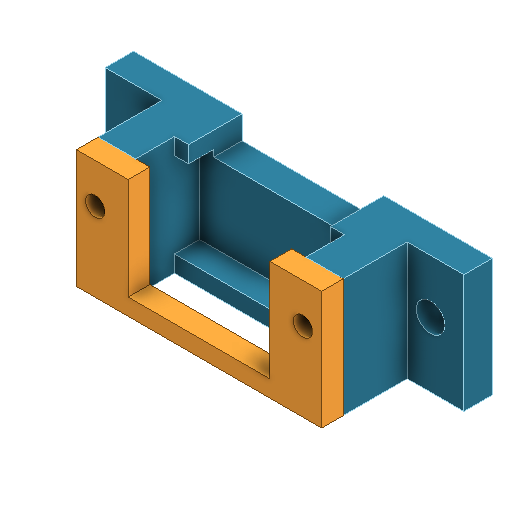
# Autodesk Inventor part: MI-305_Mount_A_Flat_Screw
Saved by Autodesk Inventor 2027 (Build 310192060, 192F)
## iProperties
Created: 2026-11-23
Part Number: MI-305_Mount_A_Flat_Screw
Material: 一般
Document SubType Name: Modeling
Designer: 王翊丞
Density: 1 g/cm^3
Appearance: 預設
Title: MI-305 A 平放螺絲款
Author: 王翊丞
Comments: MI-305 專用。以兩顆 M2 螺絲固定壓片。模型內的底座與壓片是獨立實體。
Autodesk Inventor part; units mm, degrees
sketch "平放承板草圖" plane through (0, 0, 0) normal (0, 0, 1) x (1, 0, 0)
  line L0 (-21.5, -11.95) -> (21.5, -11.95)
  line L1 (21.5, -11.95) -> (21.5, 2.25)
  line L2 (21.5, 2.25) -> (-21.5, 2.25)
  line L3 (-21.5, 2.25) -> (-21.5, -11.95)
  point P0 (0, 0)
  dimension "d0" = 21.5
  dimension "d1" = 11.95
  dimension "d2" = 43
  dimension "d3" = 14.2
  constraints: 8 end point, 2 parallel, 1 horizontal, 1 perpendicular, 1 other
  measures "d0" horizontal distance of point (0, 0) L0.start
  measures "d1" vertical distance of point (0, 0) L0.start
  measures "d2" distance of L0.start L0.end
  measures "d3" distance of L0.end L1.end
extrude "平放承板" add sketch "平放承板草圖" along normal blind 3.4
ref_plane "承托面" through (0, 0, 3.4) normal (0, 0, 1) x (1, 0, 0)
sketch "USB 插拔避空草圖" plane through (0, 0, 3.4) normal (0, 0, 1) x (1, 0, 0)
  line L0 (-8.5, -0.55) -> (8.5, -0.55)
  line L1 (8.5, -0.55) -> (8.5, 3.25)
  line L2 (8.5, 3.25) -> (-8.5, 3.25)
  line L3 (-8.5, 3.25) -> (-8.5, -0.55)
  point P0 (0, 0)
  dimension "d7" = 8.5
  dimension "d8" = 0.55
  dimension "d9" = 17
  dimension "d10" = 3.8
  constraints: 8 end point, 2 parallel, 1 horizontal, 1 perpendicular, 1 other
  measures "d7" horizontal distance of point (0, 0) L0.start
  measures "d8" vertical distance of point (0, 0) L0.start
  measures "d9" distance of L0.start L0.end
  measures "d10" distance of L0.end L1.end
extrude "USB 插拔避空" cut sketch "USB 插拔避空草圖" against normal blind 3.4
sketch "左側定位壁草圖" plane through (0, 0, 3.4) normal (0, 0, 1) x (1, 0, 0)
  line L0 (-14.7, -11.95) -> (-10.2, -11.95)
  line L1 (-10.2, -11.95) -> (-10.2, 2.25)
  line L2 (-10.2, 2.25) -> (-14.7, 2.25)
  line L3 (-14.7, 2.25) -> (-14.7, -11.95)
  point P0 (0, 0)
  dimension "d13" = 14.7
  dimension "d14" = 11.95
  dimension "d15" = 4.5
  dimension "d16" = 14.2
  constraints: 8 end point, 2 parallel, 1 horizontal, 1 perpendicular, 1 other
  measures "d13" horizontal distance of point (0, 0) L0.start
  measures "d14" vertical distance of point (0, 0) L0.start
  measures "d15" distance of L0.start L0.end
  measures "d16" distance of L0.end L1.end
extrude "左側定位壁" add sketch "左側定位壁草圖" along normal blind 7.65
sketch "右側定位壁草圖" plane through (0, 0, 3.4) normal (0, 0, 1) x (1, 0, 0)
  line L0 (10.2, -11.95) -> (14.7, -11.95)
  line L1 (14.7, -11.95) -> (14.7, 2.25)
  line L2 (14.7, 2.25) -> (10.2, 2.25)
  line L3 (10.2, 2.25) -> (10.2, -11.95)
  point P0 (0, 0)
  dimension "d19" = 10.2
  dimension "d20" = 11.95
  dimension "d21" = 4.5
  dimension "d22" = 14.2
  constraints: 8 end point, 2 parallel, 1 horizontal, 1 perpendicular, 1 other
  measures "d19" horizontal distance of point (0, 0) L0.start
  measures "d20" vertical distance of point (0, 0) L0.start
  measures "d21" distance of L0.start L0.end
  measures "d22" distance of L0.end L1.end
extrude "右側定位壁" add sketch "右側定位壁草圖" along normal blind 7.65
sketch "弧端定位擋塊草圖" plane through (0, 0, 3.4) normal (0, 0, 1) x (1, 0, 0)
  line L0 (-10.2, -11.95) -> (10.2, -11.95)
  line L1 (10.2, -11.95) -> (10.2, -9.95)
  line L2 (10.2, -9.95) -> (-10.2, -9.95)
  line L3 (-10.2, -9.95) -> (-10.2, -11.95)
  point P0 (0, 0)
  dimension "d25" = 10.2
  dimension "d26" = 11.95
  dimension "d27" = 20.4
  dimension "d28" = 2
  constraints: 8 end point, 2 parallel, 1 horizontal, 1 perpendicular, 1 other
  measures "d25" horizontal distance of point (0, 0) L0.start
  measures "d26" vertical distance of point (0, 0) L0.start
  measures "d27" distance of L0.start L0.end
  measures "d28" distance of L0.end L1.end
extrude "弧端定位擋塊" add sketch "弧端定位擋塊草圖" along normal blind 3
sketch "左肩面擋塊草圖" plane through (0, 0, 3.4) normal (0, 0, 1) x (1, 0, 0)
  line L0 (-10.2, 0.25) -> (-8.5, 0.25)
  line L1 (-8.5, 0.25) -> (-8.5, 2.25)
  line L2 (-8.5, 2.25) -> (-10.2, 2.25)
  line L3 (-10.2, 2.25) -> (-10.2, 0.25)
  point P0 (0, 0)
  dimension "d31" = 10.2
  dimension "d32" = 0.25
  dimension "d33" = 1.7
  dimension "d34" = 2
  constraints: 8 end point, 2 parallel, 1 horizontal, 1 perpendicular, 1 other
  measures "d31" horizontal distance of point (0, 0) L0.start
  measures "d32" vertical distance of point (0, 0) L0.start
  measures "d33" distance of L0.start L0.end
  measures "d34" distance of L0.end L1.end
extrude "左肩面擋塊" add sketch "左肩面擋塊草圖" along normal blind 3
sketch "右肩面擋塊草圖" plane through (0, 0, 3.4) normal (0, 0, 1) x (1, 0, 0)
  line L0 (8.5, 0.25) -> (10.2, 0.25)
  line L1 (10.2, 0.25) -> (10.2, 2.25)
  line L2 (10.2, 2.25) -> (8.5, 2.25)
  line L3 (8.5, 2.25) -> (8.5, 0.25)
  point P0 (0, 0)
  dimension "d37" = 8.5
  dimension "d38" = 0.25
  dimension "d39" = 1.7
  dimension "d40" = 2
  constraints: 8 end point, 2 parallel, 1 horizontal, 1 perpendicular, 1 other
  measures "d37" horizontal distance of point (0, 0) L0.start
  measures "d38" vertical distance of point (0, 0) L0.start
  measures "d39" distance of L0.start L0.end
  measures "d40" distance of L0.end L1.end
extrude "右肩面擋塊" add sketch "右肩面擋塊草圖" along normal blind 3
ref_plane "壓片底面" through (0, 0, 11.05) normal (0, 0, 1) x (1, 0, 0)
sketch "側壁 M2 底孔草圖" plane through (0, 0, 11.05) normal (0, 0, 1) x (1, 0, 0)
  circle A0 centre (-12.45, -2.5) radius 0.85
  circle A1 centre (12.45, -2.5) radius 0.85
  point P0 (0, 0)
  dimension "d44" = 12.45
  dimension "d45" = 2.5
  dimension "d46" = 1.7
  dimension "d47" = 12.45
  dimension "d48" = 2.5
  dimension "d49" = 1.7
  constraints: 2 centre point, 1 other
  measures "d44" horizontal distance of point (0, 0) A0.centre
  measures "d45" vertical distance of point (0, 0) A0.centre
  measures "d46" diameter of A0
  measures "d47" horizontal distance of point (0, 0) A1.centre
  measures "d48" vertical distance of point (0, 0) A1.centre
  measures "d49" diameter of A1
extrude "側壁 M2 底孔" cut sketch "側壁 M2 底孔草圖" against normal blind 4.5
sketch "平面安裝 M3 通孔草圖" plane through (0, 0, 3.4) normal (0, 0, 1) x (1, 0, 0)
  circle A0 centre (-17.5, -4.171) radius 1.7
  circle A1 centre (17.5, -4.171) radius 1.7
  point P0 (0, 0)
  dimension "d52" = 17.5
  dimension "d53" = 4.171
  dimension "d54" = 3.4
  dimension "d55" = 17.5
  dimension "d56" = 4.171
  dimension "d57" = 3.4
  constraints: 2 centre point, 1 other
  measures "d52" horizontal distance of point (0, 0) A0.centre
  measures "d53" vertical distance of point (0, 0) A0.centre
  measures "d54" diameter of A0
  measures "d55" horizontal distance of point (0, 0) A1.centre
  measures "d56" vertical distance of point (0, 0) A1.centre
  measures "d57" diameter of A1
extrude "平面安裝 M3 通孔" cut sketch "平面安裝 M3 通孔草圖" against normal blind 3.4
ref_plane "壓片頂面" through (0, 0, 13.65) normal (0, 0, 1) x (1, 0, 0)
sketch "壓框毛坯草圖" plane through (0, 0, 11.05) normal (0, 0, 1) x (1, 0, 0)
  line L0 (-14.7, -11.95) -> (14.7, -11.95)
  line L1 (14.7, -11.95) -> (14.7, 2.25)
  line L2 (14.7, 2.25) -> (-14.7, 2.25)
  line L3 (-14.7, 2.25) -> (-14.7, -11.95)
  point P0 (0, 0)
  dimension "d61" = 14.7
  dimension "d62" = 11.95
  dimension "d63" = 29.4
  dimension "d64" = 14.2
  constraints: 8 end point, 2 parallel, 1 horizontal, 1 perpendicular, 1 other
  measures "d61" horizontal distance of point (0, 0) L0.start
  measures "d62" vertical distance of point (0, 0) L0.start
  measures "d63" distance of L0.start L0.end
  measures "d64" distance of L0.end L1.end
extrude "壓框毛坯" add sketch "壓框毛坯草圖" along normal blind 2.6 separate body
sketch "U 形開口草圖" plane through (0, 0, 13.65) normal (0, 0, 1) x (1, 0, 0)
  line L0 (-8.5, -9.95) -> (8.5, -9.95)
  line L1 (8.5, -9.95) -> (8.5, 3.25)
  line L2 (8.5, 3.25) -> (-8.5, 3.25)
  line L3 (-8.5, 3.25) -> (-8.5, -9.95)
  point P0 (0, 0)
  dimension "d67" = 8.5
  dimension "d68" = 9.95
  dimension "d69" = 17
  dimension "d70" = 13.2
  constraints: 8 end point, 2 parallel, 1 horizontal, 1 perpendicular, 1 other
  measures "d67" horizontal distance of point (0, 0) L0.start
  measures "d68" vertical distance of point (0, 0) L0.start
  measures "d69" distance of L0.start L0.end
  measures "d70" distance of L0.end L1.end
extrude "U 形開口" cut sketch "U 形開口草圖" against normal blind 2.6 bodies 2
sketch "壓框 M2 通孔草圖" plane through (0, 0, 13.65) normal (0, 0, 1) x (1, 0, 0)
  circle A0 centre (-12.45, -2.5) radius 1.15
  circle A1 centre (12.45, -2.5) radius 1.15
  point P0 (0, 0)
  dimension "d73" = 12.45
  dimension "d74" = 2.5
  dimension "d75" = 2.3
  dimension "d76" = 12.45
  dimension "d77" = 2.5
  dimension "d78" = 2.3
  constraints: 2 centre point, 1 other
  measures "d73" horizontal distance of point (0, 0) A0.centre
  measures "d74" vertical distance of point (0, 0) A0.centre
  measures "d75" diameter of A0
  measures "d76" horizontal distance of point (0, 0) A1.centre
  measures "d77" vertical distance of point (0, 0) A1.centre
  measures "d78" diameter of A1
extrude "壓框 M2 通孔" cut sketch "壓框 M2 通孔草圖" against normal blind 2.6 bodies 2
equation "\"d0\" = BaseHalfX"
equation "\"d1\" = -RearY"
equation "\"d2\" = 2 * BaseHalfX"
equation "\"d3\" = FrontY - RearY"
equation "\"d4\" = PlateThickness"
equation "\"d7\" = LipX"
equation "\"d9\" = 2 * LipX"
equation "\"d11\" = PlateThickness"
equation "\"d13\" = OuterX"
equation "\"d14\" = -RearY"
equation "\"d15\" = -InnerX + OuterX"
equation "\"d16\" = FrontY - RearY"
equation "\"d17\" = RailTop - PlateThickness"
equation "\"d19\" = InnerX"
equation "\"d20\" = -RearY"
equation "\"d21\" = OuterX - InnerX"
equation "\"d22\" = FrontY - RearY"
equation "\"d23\" = RailTop - PlateThickness"
equation "\"d25\" = InnerX"
equation "\"d26\" = -RearY"
equation "\"d27\" = 2 * InnerX"
equation "\"d28\" = RearInsideY - RearY"
equation "\"d29\" = StopHeight"
equation "\"d31\" = InnerX"
equation "\"d32\" = FrontInsideY"
equation "\"d33\" = -LipX + InnerX"
equation "\"d34\" = FrontY - FrontInsideY"
equation "\"d35\" = StopHeight"
equation "\"d37\" = LipX"
equation "\"d38\" = FrontInsideY"
equation "\"d39\" = InnerX - LipX"
equation "\"d40\" = FrontY - FrontInsideY"
equation "\"d41\" = StopHeight"
equation "\"d44\" = ScrewX"
equation "\"d45\" = -ScrewY"
equation "\"d46\" = KeeperPilot"
equation "\"d47\" = ScrewX"
equation "\"d48\" = -ScrewY"
equation "\"d49\" = KeeperPilot"
equation "\"d50\" = KeeperPilotDepth"
equation "\"d52\" = 0.5 * MountPitch"
equation "\"d53\" = 0.43 * HousingDepth - ShoulderY"
equation "\"d54\" = MountHole"
equation "\"d55\" = 0.5 * MountPitch"
equation "\"d56\" = 0.43 * HousingDepth - ShoulderY"
equation "\"d57\" = MountHole"
equation "\"d58\" = PlateThickness"
equation "\"d61\" = OuterX"
equation "\"d62\" = -RearY"
equation "\"d63\" = 2 * OuterX"
equation "\"d64\" = FrontY - RearY"
equation "\"d65\" = KeeperThickness"
equation "\"d67\" = LipX"
equation "\"d68\" = -RearInsideY"
equation "\"d69\" = 2 * LipX"
equation "\"d71\" = KeeperThickness"
equation "\"d73\" = ScrewX"
equation "\"d74\" = -ScrewY"
equation "\"d75\" = KeeperScrewClear"
equation "\"d76\" = ScrewX"
equation "\"d77\" = -ScrewY"
equation "\"d78\" = KeeperScrewClear"
equation "\"d79\" = KeeperThickness"
equation "\"HousingWidth\" = 19.8"
equation "\"HousingDepth\" = 9.7"
equation "\"HousingThickness\" = 7.4"
equation "\"FitSide\" = 0.3"
equation "\"FitEnd\" = 0.25"
equation "\"TopClearance\" = 0.25"
equation "\"GripOverlap\" = 1.4"
equation "\"SideWall\" = 4.5"
equation "\"StopWall\" = 2"
equation "\"StopHeight\" = 3"
equation "\"PlateThickness\" = 3.4"
equation "\"KeeperThickness\" = 2.6"
equation "\"KeeperPilot\" = 1.7"
equation "\"KeeperScrewClear\" = 2.3"
equation "\"KeeperPilotDepth\" = 4.5"
equation "\"MountPitch\" = 35"
equation "\"MountHole\" = 3.4"
equation "\"ShoulderY\" = 0"
equation "\"InnerX\" = 0.5 * HousingWidth + FitSide"
equation "\"OuterX\" = InnerX + SideWall"
equation "\"LipX\" = 0.5 * HousingWidth - GripOverlap"
equation "\"ScrewX\" = InnerX + 0.5 * SideWall"
equation "\"RearY\" = -FitEnd + ShoulderY - HousingDepth - StopWall"
equation "\"RearInsideY\" = RearY + StopWall"
equation "\"FrontInsideY\" = ShoulderY + FitEnd"
equation "\"FrontY\" = FrontInsideY + StopWall"
equation "\"RailTop\" = HousingThickness + PlateThickness + TopClearance"
equation "\"USBOpening\" = 2 * LipX"
equation "\"d6\" = PlateThickness"
equation "\"d43\" = RailTop"
equation "\"d60\" = RailTop + KeeperThickness"
equation "\"BaseHalfX\" = 21.5"
equation "\"ScrewY\" = -2.5"
